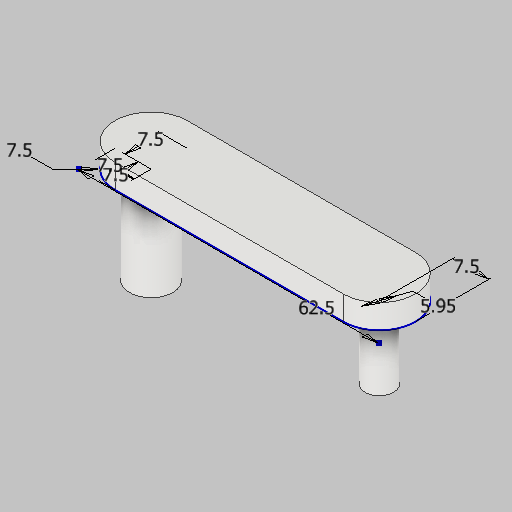
# Autodesk Inventor part: CAM Shaft 3
Saved by Autodesk Inventor 2026.1 (Build 301233000, 233)
## iProperties
Created: 2026-10-29
Part Number: CAM Shaft 3
Material: Generic
Document SubType Name: Modeling
Designer: FerdiaComerford
Density: 1 g/cm^3
Appearance: Default
Author: FerdiaComerford
Revision Number: 0
Autodesk Inventor part; units mm, degrees
ref_plane "YZ Plane" through (0, 0, 0) normal (1, 0, 0) x (0, 1, 0)
ref_plane "XZ Plane" through (0, 0, 0) normal (0, 1, 0) x (-1, 0, 0)
ref_plane "XY Plane" through (0, 0, 0) normal (0, 0, 1) x (1, 0, 0)
sketch "Sketch7" plane through (0, 0, 0) normal (0, 1, 0) x (-1, 0, 0)
  line L0 (2.6, 1.6) -> (-2.6, 1.6)
  line L1 (-2.6, 1.6) -> (-2.6, -1.6)
  line L2 (-2.6, -1.6) -> (2.6, -1.6)
  line L3 (2.6, -1.6) -> (2.6, 1.6)
  line L4 (2.6, 1.6) -> (-2.6, -1.6) construction
  line L5 (-2.6, 1.6) -> (2.6, -1.6) construction
  circle A0 centre (0, 0) radius 4.5
  dimension "d12" = 3.2
  dimension "d13" = 5.2
  dimension "d14" = 9
  constraints: 12 end point, 2 midpoint, 2 parallel, 1 centre point, 1 coincident, 1 horizontal, 1 perpendicular
  measures "d12" distance of L2.end L0.start
  measures "d13" distance of L1.end L2.end
  measures "d14" diameter of A0
extrude "Extrusion3" add sketch "Sketch7" along normal blind 20
sketch "Sketch8" plane through (0, 20, 0) normal (0, 1, 0) x (1, 0, 0)
  line L0 (0, -7.5) -> (47.5, -7.5)
  line L1 (55, 0) -> (55, 0)
  line L2 (47.5, 7.5) -> (0, 7.5)
  line L3 (-7.5, 0) -> (-7.5, 0)
  circle A0 centre (47.5, 0) radius 2.975
  arc A1 (-7.5, 0) -> (0, -7.5) centre (0, 0) ccw
  arc A2 (0, 7.5) -> (-7.5, 0) centre (0, 0) ccw
  arc A3 (55, 0) -> (47.5, 7.5) centre (47.5, 0) ccw
  arc A4 (47.5, -7.5) -> (55, 0) centre (47.5, 0) ccw
  point P0 (0, 0)
  point P1 (-7.5, -7.5)
  point P2 (55, -7.5)
  dimension "d17" = 7.5
  dimension "d18" = 7.5
  dimension "d19" = 7.5
  dimension "d20" = 62.5
  dimension "d21" = 5.95
  dimension "d22" = 7.5
  dimension "d23" = 7.5
  constraints: 8 end point, 8 point on circle, 8 tangent, 5 centre point, 4 point on line, 3 equal radius, 2 parallel, 1 horizontal, 1 perpendicular
  measures "d17" distance from line of L3 point (0, 0)
  measures "d18" distance from line of L0 point (0, 0)
  measures "d19" distance from line of L2 point (0, 0)
  measures "d20" distance of point (-7.5, -7.5) point (55, -7.5)
  measures "d21" diameter of A0
  measures "d22" distance from line of L1 A0.centre
  measures "d23" radius of A1
extrude "Extrusion4" add sketch "Sketch8" along normal blind 5
extrude "Extrusion5" add sketch "Sketch8" along normal blind 5 and the other way blind 15 contours A0
body "Solid3"
